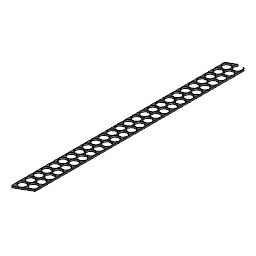
holder_52_FINAL (Autodesk Fusion 360 design; units mm, degrees)
part number: 2026-07-22-22-33-43-266
Autodesk Fusion 360 part; units mm, degrees
sketch "Sketch1" plane through (0, 0, 0) normal (0, 0, 1) x (1, 0, 0)
  line L0 (0, 0) -> (38.2339, 0)
  line L1 (38.2339, 0) -> (38.2339, 532.5)
  line L2 (38.2339, 532.5) -> (0, 532.5)
  line L3 (0, 532.5) -> (0, 0)
extrude "Extrude1" add sketch "Sketch1" along normal blind 4
fillet "Fillet1" radius 3 4 edges at (0, 532.5, 2) (38.2339, 532.5, 2) (38.2339, 0, 2) (0, 0, 2)
sketch "Sketch2" plane through (0, 0, 0) normal (0, 0, 1) x (1, 0, 0)
  circle A0 centre (10.5, 17.5) radius 9.5
extrude "Extrude2" cut sketch "Sketch2" along normal blind 6
pattern_linear "R-Pattern1" count 26 spacing 19.9 along (0, 1, 0) count 3 spacing 0 along (0, 1, 0) of "Extrude2"
sketch "Sketch3" plane through (0, 0, 0) normal (0, 0, 1) x (1, 0, 0)
  circle A0 centre (27.7339, 27.45) radius 9.5
extrude "Extrude3" cut sketch "Sketch3" along normal blind 6
pattern_linear "R-Pattern2" count 26 spacing 19.9 along (0, 1, 0) count 3 spacing 0 along (0, 1, 0) of "Extrude3"
sketch "Sketch4" plane through (0, 0, 0) normal (0, 0, 1) x (1, 0, 0)
  line L0 (0, -0.6865) -> (38.2339, 21.3878)
  line L1 (38.2339, 21.3878) -> (38.2339, -50)
  line L2 (38.2339, -50) -> (0, -50)
  line L3 (0, -50) -> (0, -0.6865)
extrude "Extrude4" cut sketch "Sketch4" along normal blind 6
sketch "Sketch5" plane through (0, 0, 0) normal (0, 0, 1) x (1, 0, 0)
  line L0 (0, 521.0622) -> (38.2339, 543.1365)
  line L1 (38.2339, 543.1365) -> (38.2339, 582.5)
  line L2 (38.2339, 582.5) -> (0, 582.5)
  line L3 (0, 582.5) -> (0, 521.0622)
extrude "Extrude5" cut sketch "Sketch5" along normal blind 6
fillet "Fillet2" radius 2 2 edges at (0, 521.0622, 2) (38.2339, 21.3878, 2)
named bodies: "holder_52_FINAL"
